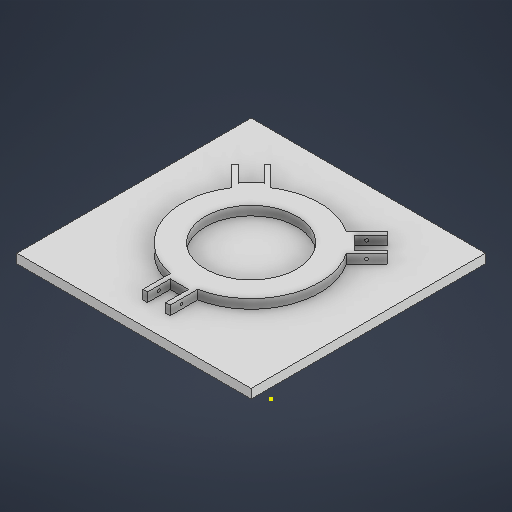
# Autodesk Inventor part: TopPlate
Saved by Autodesk Inventor 2027.2 (Build 312334000, 334)
## iProperties
Created: 2026-11-19
Part Number: TopPlate
Material: Generic
Document SubType Name: Modeling
Designer: junha
Density: 1 g/cm^3
Appearance: Default
Author: junha
Autodesk Inventor part; units mm, degrees
ref_plane "YZ Plane" through (0, 0, 0) normal (1, 0, 0) x (0, 1, 0)
ref_plane "XZ Plane" through (0, 0, 0) normal (0, 1, 0) x (-1, 0, 0)
ref_plane "XY Plane" through (0, 0, 0) normal (0, 0, 1) x (1, 0, 0)
sketch "Sketch1" plane through (0, 0, 0) normal (0, 1, 0) x (-1, 0, 0)
  line L0 (0, 0) -> (256, 0)
  line L1 (256, 0) -> (256, -256)
  line L2 (256, -256) -> (0, -256)
  line L3 (0, -256) -> (0, 0)
  dimension "d0" = 256
  dimension "d1" = 256
  constraints: 8 end point, 2 parallel, 1 horizontal, 1 perpendicular
  measures "d0" distance of L1.end L2.end
  measures "d1" distance of L0.end L1.end
extrude "Extrusion1" add sketch "Sketch1" along normal blind 10
sketch "Sketch2" plane through (0, 10, 0) normal (0, 1, 0) x (1, 0, 0)
  line L0 (-256, 256) -> (-256, 0) projected
  line L1 (-256, 128) -> (0, 128)
  line L2 (0, 0) -> (0, 256) projected
  line L3 (0, 256) -> (-256, 256) projected
  line L4 (-128, 256) -> (-128, 0)
  line L5 (-256, 0) -> (0, 0) projected
  circle A0 centre (-128, 128) radius 50
  circle A1 centre (-128, 128) radius 75
  line L6 (-256, 256) -> (0, 0)
  line L7 (0, 256) -> (-256, 0)
  line L8 (-113.0597, 54.5032) -> (-113.0597, 24.5032)
  line L9 (-142.9248, 54.5) -> (-142.9248, 24.5032)
  line L10 (-142.9248, 24.5032) -> (-137.9248, 24.5032)
  line L11 (-137.9248, 24.5032) -> (-137.9248, 49.5032)
  line L12 (-113.0597, 24.5032) -> (-118.0597, 24.5032)
  line L13 (-118.0597, 24.5032) -> (-117.9248, 49.5032)
  line L14 (-117.9248, 49.5032) -> (-137.9248, 49.5032)
  line L15 (-74.967, 181.033) -> (-71.4315, 184.5685)
  line L16 (-71.4315, 184.5685) -> (-64.3604, 177.4975)
  line L17 (-71.4315, 184.5685) -> (-78.5025, 191.6396)
  line L18 (-78.5025, 191.6396) -> (-60.8249, 209.3173)
  line L19 (-60.8249, 209.3173) -> (-64.3604, 212.8528)
  line L20 (-64.3604, 212.8528) -> (-86.6451, 190.5681)
  line L21 (-64.3604, 177.4975) -> (-46.6827, 195.1751)
  line L22 (-46.6827, 195.1751) -> (-43.1472, 191.6396)
  line L23 (-43.1472, 191.6396) -> (-65.4319, 169.3549)
  line L24 (-181.033, 181.033) -> (-184.5685, 184.5685)
  line L25 (-184.5685, 184.5685) -> (-177.4975, 191.6396)
  line L26 (-184.5685, 184.5685) -> (-191.6396, 177.4975)
  line L27 (-191.6396, 177.4975) -> (-209.3173, 195.1751)
  line L28 (-209.3173, 195.1751) -> (-212.8528, 191.6396)
  line L29 (-212.8528, 191.6396) -> (-190.5681, 169.3549)
  line L30 (-177.4975, 191.6396) -> (-195.1751, 209.3173)
  line L31 (-195.1751, 209.3173) -> (-191.6396, 212.8528)
  line L32 (-191.6396, 212.8528) -> (-169.3549, 190.5681)
  dimension "d5" = 150
  dimension "d4" = 100
  dimension "d7" = 30
  dimension "d9" = 5
  dimension "d10" = 25
  dimension "d11" = 5
  dimension "d12" = 20
  dimension "d23" = 5
  dimension "d24" = 10
  dimension "d25" = 10
  dimension "d27" = 10
  dimension "d28" = 10
  dimension "d29" = 25
  dimension "d30" = 25
  dimension "d31" = 5
  constraints: 58 end point, 16 perpendicular, 5 midpoint, 4 point on line, 1 centre point, 1 coincident, 1 vertical, 10 other
  measures "d4" diameter of A0
  measures "d7" distance of L8.start L8.end
  measures "d9" distance of L9.end L10.end
  measures "d10" distance of L10.end L11.end
  measures "d11" distance of L8.end L12.end
  measures "d12" distance of L13.end L11.end
  measures "d23" distance of L15.start L15.end
  measures "d24" distance of L15.end L16.end
  measures "d25" distance of L15.end L17.end
  measures "d27" distance of L24.end L25.end
  measures "d28" distance of L24.end L26.end
  measures "d29" distance of L26.end L27.end
  measures "d30" distance of L25.end L30.end
  measures "d31" distance of L30.end L31.end
extrude "Extrusion2" add sketch "Sketch2" along normal blind 10 contours L25 L30 L31 L32 A1 L6 | L6 A1 L29 L28 L27 L26 | A1 L6 A0 L1 | L1 A0 L7 A1 | A1 L7 A0 L4 | L4 A0 L6 A1 | L7 A0 L4 A1 | L16 L21 L22 L23 A1 L7 | L7 A1 L20 L19 L18 L17 | L14 L11 L10 L9 A1 L4 | L4 A1 L8 L12 L13 L14 | A1 L6 A0 L1 | L1 A0 L7 A1 | L4 A0 L6 A1
sketch "Sketch3" plane through (-43.1472, 10, -191.6396) normal (0.7071, 0, 0.7071) x (0.7071, 0, -0.7071)
  line L0 (-31.5153, 0) -> (-31.5153, 10) projected
  line L1 (0, 0) -> (0, 10) projected
  line L2 (0, 10) -> (-31.5153, 10) projected
  line L3 (0, 10) -> (-15.7577, 10)
  line L4 (-25, 0) -> (0, 0) projected
  circle A0 centre (-15.7577, 5) radius 1.6
  point P0 (-105, -10)
  dimension "d34" = 3.2
  constraints: 2 end point, 1 centre point, 1 midpoint
  measures "d34" diameter of A0
extrude "Extrusion3" cut sketch "Sketch3" against normal blind 30
sketch "Sketch4" plane through (-113.0597, 10, -24.5032) normal (1, 0, 0) x (0, 0, -1)
  line L0 (30, 0) -> (30, 10) projected
  line L1 (0, 0) -> (0, 10) projected
  line L2 (0, 10) -> (25, 10) projected
  line L3 (-24.5032, 0) -> (231.4968, 0) projected
  circle A0 centre (12.5, 5) radius 1.6
  point P0 (-24.5032, -10)
  dimension "d37" = 3.2
  constraints: 1 centre point
  measures "d37" diameter of A0
extrude "Extrusion4" cut sketch "Sketch4" against normal blind 30
sketch "Sketch5" plane through (-191.6396, 10, -212.8528) normal (0.7071, 0, -0.7071) x (-0.7071, 0, -0.7071)
  point P0 (-286.0193, -10)
sketch "Sketch6" plane through (-190.5681, 10, -169.3549) normal (-0.7071, 0, 0.7071) x (0.7071, 0, 0.7071)
  line L0 (0, 0) -> (0, 10) projected
  line L1 (-31.5153, 0) -> (-31.5153, 10) projected
  line L2 (0, 10) -> (-31.5153, 10) projected
  line L3 (-6.5153, 0) -> (-31.5153, 0) projected
  circle A0 centre (-15.7577, 5) radius 1.6
  point P0 (254.504, -10)
  dimension "d40" = 3.2
  constraints: 1 centre point
  measures "d40" diameter of A0
extrude "Extrusion5" cut sketch "Sketch6" against normal blind 30
body "Solid1"
